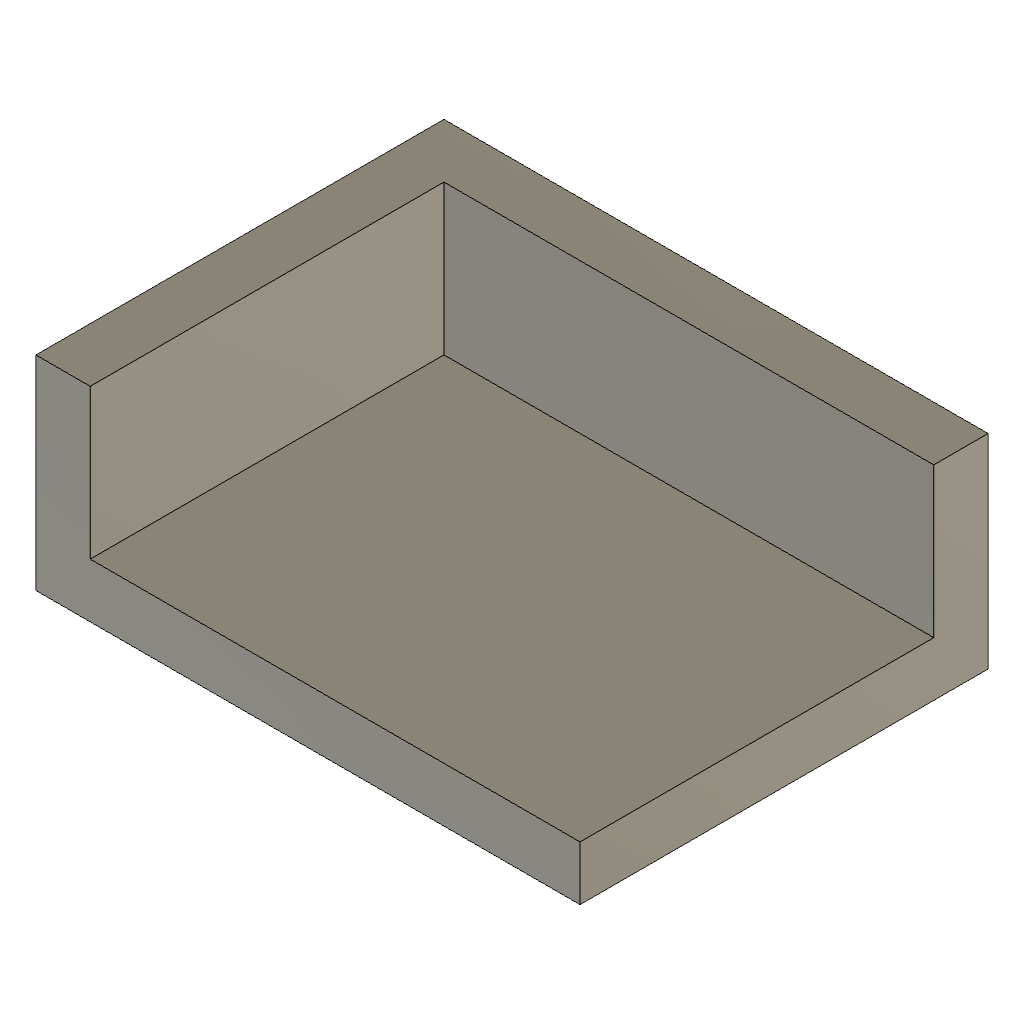
vendor_ShellOpenCorner (Autodesk Fusion 360 design; units mm, degrees)
Autodesk Fusion 360 part; units mm, degrees
sketch "Base Sketch" plane through (0, 0, 0) normal (0, 0, 1) x (1, 0, 0)
  line L0 (0, 0) -> (40, 0)
  line L1 (40, 0) -> (40, 30)
  line L2 (40, 30) -> (0, 30)
  line L3 (0, 30) -> (0, 0)
extrude "Base Extrude" add sketch "Base Sketch" along normal blind 15
shell "Open corner" thickness 4 removed faces 3 at (13.3333, 0, 10) at (40, 10, 10) at (13.3333, 20, 15)
equation "height = 20.0 mm"
